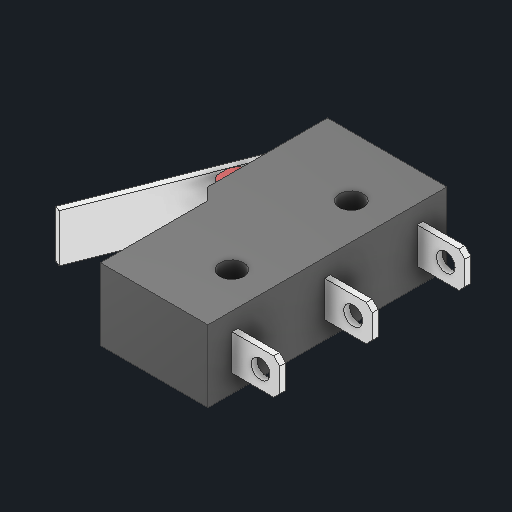
# Autodesk Inventor part: 리밋스위치
Saved by Autodesk Inventor 2026.2 (Build 302298000, 298)
## iProperties
Created: 2025-09-11
Part Number: 리밋스위치
Material: ABS 플라스틱
Document SubType Name: Modeling
Designer: work
Density: 1.06 g/cm^3
Appearance: 매끄러움 - 흰색
Author: work
Autodesk Inventor part; units mm, degrees
ref_plane "YZ Plane" through (0, 0, 0) normal (1, 0, 0) x (0, 1, 0)
ref_plane "XZ Plane" through (0, 0, 0) normal (0, 1, 0) x (-1, 0, 0)
ref_plane "XY Plane" through (0, 0, 0) normal (0, 0, 1) x (1, 0, 0)
sketch "스케치1" plane through (0, 0, 0) normal (0, 1, 0) x (-1, 0, 0)
  line L0 (0, 0) -> (10, 0)
  line L1 (10, 0) -> (10, -20)
  line L2 (10, -20) -> (0, -20)
  line L3 (0, -20) -> (0, 0)
  line L4 (10, -10) -> (10, -10)
  line L5 (9, -9) -> (9, 0)
  line L6 (9, -9) -> (10, -10)
  line L7 (10, -10) -> (0, -10) construction
  circle A0 centre (3, -5) radius 1
  circle A1 centre (3, -15) radius 1
  point P0 (9, -10)
  dimension "d0" = 10
  dimension "d1" = 20
  dimension "d2" = 1
  dimension "d3" = 1
  dimension "d4" = 1
  dimension "d5" = 2
  dimension "d6" = 6
  dimension "d7" = 4
  constraints: 16 end point, 3 point on line, 2 centre point, 2 horizontal, 2 midpoint, 2 parallel, 2 perpendicular, 1 symmetric about line, 1 other
  measures "d0" distance of L1.end L2.end
  measures "d1" distance of L0.end L1.end
  measures "d2" distance of L4.start point (9, -10)
  measures "d3" distance of L5.start point (9, -10)
  measures "d4" distance of L4.end point (9, -10)
  measures "d5" diameter of A0
  measures "d6" distance edge to line of A0 L1
  measures "d7" distance edge to line of A0 L0
extrude "돌출1" add sketch "스케치1" along normal blind 6 contours L0 L5 L6 L1 L2 L3
sketch "스케치2" plane through (-10, 0, -20) normal (-1, 0, 0) x (0, 0, 1)
  line L0 (6, 1) -> (8.5, 1)
  line L1 (8.5, 1) -> (8.5, 5)
  line L2 (8.5, 5) -> (6, 5)
  line L3 (6, 5) -> (6, 1)
  line L4 (0, 0) -> (0, 6) projected
  line L5 (0, 3) -> (20, 3) construction
  line L6 (20, 0) -> (20, 6) projected
  point P0 (6, 3)
  dimension "d10" = 6
  dimension "d11" = 2.5
  dimension "d12" = 4
  constraints: 10 end point, 3 midpoint, 2 parallel, 1 horizontal, 1 perpendicular, 1 point on line
  measures "d10" distance between parallel lines of L4 L3
  measures "d11" distance between parallel lines of L1 L3
  measures "d12" distance between parallel lines of L2 L0
extrude "돌출2" add sketch "스케치2" along normal blind 1.5
fillet "모깎기1" radius 1 2 edges at (-11.5, 3, -14) (-11.5, 3, -11.5)
sketch "스케치3" plane through (-10, 1, -14) normal (0, -1, 0) x (1, 0, 0)
  line L0 (0, -6) -> (0, 4) projected
  line L1 (0, -3) -> (-5.4947, 10.9574)
  line L2 (10, -6) -> (0, -6) projected
  line L3 (-5.4947, 10.9574) -> (-5.9599, 10.7742)
  line L4 (-5.9599, 10.7742) -> (0, -4.365)
  arc A0 (-0.5, 2.5) -> (-1.5, 1.5) centre (-0.5, 1.5) ccw projected
  line L5 (-1.5, 1) -> (-1.5, 1.5) projected
  arc A1 (-1.5, 1) -> (-0.5, 0) centre (-0.5, 1) ccw projected
  line L6 (0, 0) -> (-0.5, 0) projected
  line L7 (0, 2.5) -> (0, 0) projected
  line L8 (0, 2.5) -> (-0.5, 2.5) projected
  arc A2 (-1.5, 1) -> (-0.5, 0) centre (-0.5, 1) ccw projected
  point P0 (10, 14)
  dimension "d16" = 15
  dimension "d17" = 3
  dimension "d18" = 0.5
  dimension "d19" = 90
  constraints: 6 end point, 2 point on line, 1 parallel, 1 tangent
  measures "d16" distance of L1.start L1.end
  measures "d17" distance from line of L2 L1.start
  measures "d18" distance of L1.end L3.end
  measures "d19" angle of L1 L3
extrude "돌출3" add sketch "스케치3" against normal up to surface (4 mm away) contours L4 L3 L1 L0
sketch "스케치4" plane through (0, 0, 0) normal (1, 0, 0) x (0, 0, -1)
  line L0 (0, 0) -> (0, 6) projected
  line L1 (0, 3) -> (20, 3) construction
  line L2 (20, 0) -> (20, 6) projected
  line L3 (2.5, 1.5) -> (2, 1.5)
  line L4 (2, 1.5) -> (2, 4.5)
  line L5 (2, 4.5) -> (2.5, 4.5)
  line L6 (2.5, 4.5) -> (2.5, 1.5)
  line L7 (10.25, 1.5) -> (9.75, 1.5)
  line L8 (9.75, 1.5) -> (9.75, 4.5)
  line L9 (9.75, 4.5) -> (10.25, 4.5)
  line L10 (10.25, 4.5) -> (10.25, 1.5)
  line L11 (18, 1.5) -> (17.5, 1.5)
  line L12 (17.5, 1.5) -> (17.5, 4.5)
  line L13 (17.5, 4.5) -> (18, 4.5)
  line L14 (18, 4.5) -> (18, 1.5)
  line L15 (20, 0) -> (10, 0) projected
  line L16 (10, 0) -> (10, 6) construction
  line L17 (10, 0) -> (10, 6)
  point P0 (2.5, 3)
  point P1 (10.25, 3)
  point P2 (18, 3)
  point P3 (10, 1.5)
  dimension "d22" = 0.5
  dimension "d23" = 3
  dimension "d24" = 0.5
  dimension "d25" = 3
  dimension "d26" = 0.5
  dimension "d27" = 3
  dimension "d28" = 2
  dimension "d29" = 2
  constraints: 28 end point, 7 equal length, 7 midpoint, 4 point on line, 3 horizontal, 3 perpendicular
  measures "d22" distance of L4.end L5.end
  measures "d23" distance of L3.end L4.end
  measures "d24" distance of L8.end L9.end
  measures "d25" distance of L7.end L8.end
  measures "d26" distance of L12.end L13.end
  measures "d27" distance of L11.end L12.end
  measures "d28" distance between parallel lines of L2 L14
  measures "d29" distance from line of point (0, 3) L4
extrude "돌출4" add sketch "스케치4" along normal blind 4
chamfer "모따기1" distance 0.5 angle 45 6 edges at (4, 1.5, -17.75) (4, 1.5, -10) (4, 1.5, -2.25) (4, 4.5, -2.25) (4, 4.5, -10) (4, 4.5, -17.75)
sketch "스케치5" plane through (0, 1.5, -18) normal (0, 0, -1) x (-1, 0, 0)
  circle A0 centre (-2.4, 1.5) radius 0.7856
  line L0 (0, 0) -> (-3.5, 0) projected
  line L1 (-4, 0.5) -> (-4, 2.5) projected
  point P0 (0, -1.5)
  dimension "d35" = 1.5
  dimension "d36" = 1.6
  constraints: 1 centre point
  measures "d35" distance from line of L0 A0.centre
  measures "d36" distance from line of A0.centre L1
extrude "돌출5" cut sketch "스케치5" against normal through all
equation "\"d4\" = d3"
